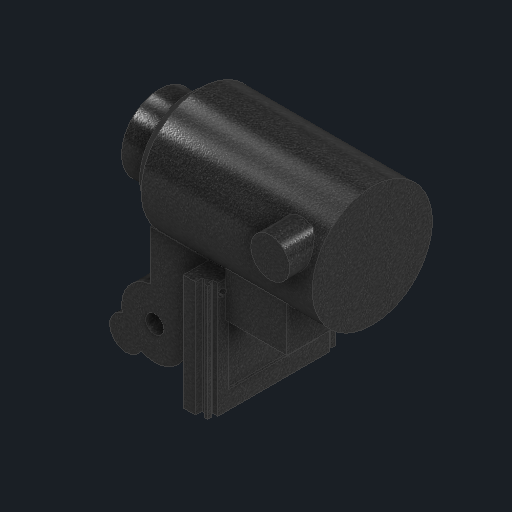
# Autodesk Inventor part: ra_housing
Saved by Autodesk Inventor 2027.1 (Build 311270010, 270A)
## iProperties
Created: 2026-11-03
Part Number: ra_housing
Material: Generic
Description: CG-5 RA axis housing with worm block, flat bit, latitude lug (estimated from photos)
Document SubType Name: Modeling
Designer: Claude (from photos)
Density: 1 g/cm^3
Appearance: Black Cast
Author: alexg
Autodesk Inventor part; units mm, degrees
sketch "RA housing body sketch" plane through (0, 0, 0) normal (0, 0, 1) x (1, 0, 0)
  line L0 (-47, 0) -> (95, 0)
  line L1 (95, 0) -> (95, 40)
  line L2 (95, 40) -> (-19, 40)
  line L3 (-19, 40) -> (-27, 33)
  line L4 (-27, 33) -> (-27, 25)
  line L5 (-27, 25) -> (-47, 25)
  line L6 (-47, 25) -> (-47, 0)
  constraints: 14 end point
revolve "RA housing body" add sketch "RA housing body sketch" angle 360 about axis through (-47, 0, 0) along (1, 0, 0)
sketch "Pivot web sketch" plane through (0, 0, 0) normal (0, 0, 1) x (1, 0, 0)
  line L0 (-26, -85) -> (15, -85)
  line L1 (15, -85) -> (15, -30)
  line L2 (15, -30) -> (-26, -30)
  line L3 (-26, -30) -> (-26, -85)
  constraints: 8 end point, 2 parallel, 1 horizontal, 1 perpendicular
extrude "Pivot web" add sketch "Pivot web sketch" along normal mid plane 54
sketch "Latitude pivot lug sketch" plane through (0, 0, 0) normal (0, 0, 1) x (1, 0, 0)
  circle A0 centre (-23, -85) radius 22
  constraints: 1 centre point
extrude "Latitude pivot lug" add sketch "Latitude pivot lug sketch" along normal mid plane 54
sketch "Latitude stem sketch" plane through (0, 0, 0) normal (0, 0, 1) x (1, 0, 0)
  line L0 (-17.459, -92.0921) -> (-36.3713, -106.868)
  line L1 (-36.3713, -106.868) -> (-47.4532, -92.6838)
  line L2 (-47.4532, -92.6838) -> (-28.541, -77.9079)
  line L3 (-28.541, -77.9079) -> (-17.459, -92.0921)
  constraints: 8 end point
extrude "Latitude stem" add sketch "Latitude stem sketch" along normal mid plane 54
sketch "Latitude bolt tab sketch" plane through (0, 0, 0) normal (0, 0, 1) x (1, 0, 0)
  circle A0 centre (-41.9123, -99.7759) radius 11
  constraints: 1 centre point
extrude "Latitude bolt tab" add sketch "Latitude bolt tab sketch" along normal mid plane 54
ref_plane "Work Plane1" through (0, 0, 30) normal (0, 0, 1) x (1, 0, 0)
sketch "Latitude pivot bore sketch" plane through (0, 0, 30) normal (0, 0, 1) x (1, 0, 0)
  circle A0 centre (-23, -85) radius 6
  constraints: 1 centre point
extrude "Latitude pivot bore" cut sketch "Latitude pivot bore sketch" against normal blind 60
ref_plane "Work Plane2" through (0, -54, 0) normal (0, 1, 0) x (-1, 0, 0)
sketch "RA worm block sketch" plane through (0, -54, 0) normal (0, 1, 0) x (-1, 0, 0)
  line L0 (-29.4, -32) -> (-70, -32)
  line L1 (-70, -32) -> (-70, 32)
  line L2 (-70, 32) -> (-29.4, 32)
  line L3 (-29.4, 32) -> (-29.4, -32)
  constraints: 8 end point, 2 parallel, 1 horizontal, 1 perpendicular
extrude "RA worm block" add sketch "RA worm block sketch" along normal blind 39
ref_plane "Work Plane3" through (0, -54, 0) normal (0, 1, 0) x (-1, 0, 0)
sketch "Worm carrier pocket sketch" plane through (0, -54, 0) normal (0, 1, 0) x (-1, 0, 0)
  line L0 (-29.4, -22) -> (-45, -22)
  line L1 (-45, -22) -> (-45, 22)
  line L2 (-45, 22) -> (-29.4, 22)
  line L3 (-29.4, 22) -> (-29.4, -22)
  constraints: 8 end point, 2 parallel, 1 horizontal, 1 perpendicular
extrude "Worm carrier pocket" cut sketch "Worm carrier pocket sketch" along normal blind 6
ref_plane "Work Plane4" through (0, -48, 0) normal (0, 1, 0) x (-1, 0, 0)
sketch "Carrier M5 tapped holes sketch" plane through (0, -48, 0) normal (0, 1, 0) x (-1, 0, 0)
  circle A0 centre (-39, 13) radius 2.6
  circle A1 centre (-39, -13) radius 2.6
  circle A2 centre (-39, 0) radius 2.6
  constraints: 3 centre point
extrude "Carrier M5 tapped holes" cut sketch "Carrier M5 tapped holes sketch" along normal blind 18
ref_plane "Work Plane5" through (0, -106.8, 0) normal (0, 1, 0) x (-1, 0, 0)
sketch "Flat bit (dovetail tongue for the frame) sketch" plane through (0, -106.8, 0) normal (0, 1, 0) x (-1, 0, 0)
  line L0 (-29.4, 37.3) -> (-25.8, 37.3)
  line L1 (-25.8, 37.3) -> (-25.8, 39.7)
  line L2 (-25.8, 39.7) -> (-27.8, 39.7)
  line L3 (-27.8, 39.7) -> (-27.8, 42.4)
  line L4 (-27.8, 42.4) -> (-25.8, 42.4)
  line L5 (-25.8, 42.4) -> (-23, 39.6)
  line L6 (-23, 39.6) -> (-21.2, 39.6)
  line L7 (-21.2, 39.6) -> (-21.2, 44)
  line L8 (-21.2, 44) -> (-13, 44)
  line L9 (-13, 44) -> (-13, -44)
  line L10 (-13, -44) -> (-21.2, -44)
  line L11 (-21.2, -44) -> (-21.2, -39.6)
  line L12 (-21.2, -39.6) -> (-23, -39.6)
  line L13 (-23, -39.6) -> (-25.8, -42.4)
  line L14 (-25.8, -42.4) -> (-27.8, -42.4)
  line L15 (-27.8, -42.4) -> (-27.8, -39.7)
  line L16 (-27.8, -39.7) -> (-25.8, -39.7)
  line L17 (-25.8, -39.7) -> (-25.8, -37.3)
  line L18 (-25.8, -37.3) -> (-29.4, -37.3)
  line L19 (-29.4, -37.3) -> (-29.4, 37.3)
  constraints: 40 end point
extrude "Flat bit (dovetail tongue for the frame)" add sketch "Flat bit (dovetail tongue for the frame) sketch" along normal blind 76.8
ref_plane "Work Plane6" through (0, -106.8, 0) normal (0, 1, 0) x (-1, 0, 0)
sketch "Flat bit locking screw hole M4 sketch" plane through (0, -106.8, 0) normal (0, 1, 0) x (-1, 0, 0)
  circle A0 centre (-26.5, 0) radius 2.05
  constraints: 1 centre point
extrude "Flat bit locking screw hole M4" cut sketch "Flat bit locking screw hole M4 sketch" along normal blind 10
ref_plane "Work Plane7" through (13, 0, 0) normal (1, 0, 0) x (0, 1, 0)
sketch "Flat bit axial M5 hole sketch" plane through (13, 0, 0) normal (1, 0, 0) x (0, 1, 0)
  circle A0 centre (-37, 34.5) radius 2.6
  constraints: 1 centre point
extrude "Flat bit axial M5 hole" cut sketch "Flat bit axial M5 hole sketch" along normal blind 17
ref_plane "Work Plane8" through (29.4, 0, 0) normal (1, 0, 0) x (0, 1, 0)
sketch "Flat bit face recess sketch" plane through (29.4, 0, 0) normal (1, 0, 0) x (0, 1, 0)
  line L0 (-95, -30) -> (-48, -30)
  line L1 (-48, -30) -> (-48, 30)
  line L2 (-48, 30) -> (-95, 30)
  line L3 (-95, 30) -> (-95, -30)
  constraints: 8 end point, 2 parallel, 1 horizontal, 1 perpendicular
extrude "Flat bit face recess" cut sketch "Flat bit face recess sketch" against normal blind 1.5
ref_plane "Work Plane9" through (0, 0, 30) normal (0, 0, 1) x (1, 0, 0)
sketch "RA lock pad sketch" plane through (0, 0, 30) normal (0, 0, 1) x (1, 0, 0)
  circle A0 centre (78, 16) radius 13
  constraints: 1 centre point
extrude "RA lock pad" add sketch "RA lock pad sketch" along normal blind 21
ref_plane "Work Plane10" through (-47, 0, 0) normal (1, 0, 0) x (0, 1, 0)
sketch "Polar scope bore sketch" plane through (-47, 0, 0) normal (1, 0, 0) x (0, 1, 0)
  circle A0 centre (0, 0) radius 13
  constraints: 1 centre point
extrude "Polar scope bore" cut sketch "Polar scope bore sketch" along normal blind 30
ref_plane "FRAME - flat bit front face (frame back slides on here)" through (29.4, 0, 0) normal (1, 0, 0) x (0, 1, 0)
ref_plane "Worm block end face +Z (nut seat, brass shaft)" through (0, 0, 32) normal (0, 0, 1) x (1, 0, 0)
ref_plane "Worm block end face -Z (knob seat)" through (0, 0, -32) normal (0, 0, 1) x (1, 0, 0)
ref_plane "MOTOR MOUNT - worm block bottom face (carrier bolts)" through (0, -54, 0) normal (0, 1, 0) x (-1, 0, 0)
body "Solid1"
